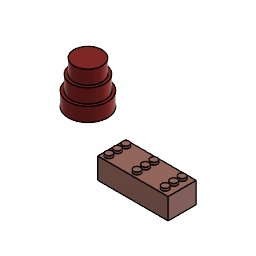
elipse (Autodesk Fusion 360 design; units mm, degrees)
part number: 2026-08-22-14-53-42-305
Autodesk Fusion 360 part; units mm, degrees
sketch "Sketch1" plane through (0, 0, 0) normal (0, 1, 0) x (1, 0, 0)
  ellipse E0 centre (13.4797, -9.3132) end of major axis (-45.8309, 16.9109) minor radius 24.1284
  line L0 (72.7902, -35.5373) -> (-45.8309, 16.9109) construction
  line L1 (23.2368, 12.7543) -> (3.7225, -31.3808) construction
  constraint coincident E0 L0.start
  constraint coincident E0 L0.end
  constraint coincident E0 L1.start
  constraint coincident E0 L1.end
sketch "Sketch2" plane through (0, 0, 0) normal (0, -1, 0) x (1, 0, 0)
  ellipse E0 centre (13.4797, 9.3132) end of major axis (-45.8309, -16.9109) minor radius 24.1284
  arc A0 (72.4234, 36.2739) -> (60.6973, -35.3427) centre (12.6561, 9.2916) ccw
  line L0 (-160.8173, -80.7542) -> (-249.1179, -79.1962) construction
  line L1 (-249.1179, -79.1962) -> (-248.7164, -56.4403) construction
  line L2 (-248.7164, -56.4403) -> (-160.4158, -57.9983) construction
  line L3 (-160.4158, -57.9983) -> (-160.8173, -80.7542) construction
  circle A1 centre (-98.7081, 34.943) radius 10
  circle A2 centre (-98.7081, 34.943) radius 12
  circle A3 centre (-98.7081, 34.943) radius 14
  dimension "d5" = 10
  dimension "d7" = 20
  dimension "d8" = 2
  dimension "d9" = 2
  constraint coincident E0 A0.start
  measures "d7" diameter of A1
sketch "Sketch3" plane through (0, 0, 0) normal (0, -1, 0) x (1, 0, 0)
extrude "Extrude6" add sketch "Sketch2" against normal blind 30 contours A1 makes body 1
extrude "Extrude7" add sketch "Sketch2" against normal blind 20 contours A2 bodies 1
extrude "Extrude8" add sketch "Sketch2" against normal blind 10 contours A3 bodies 1
sketch "Sketch4" plane through (0, 0, 0) normal (0, 1, 0) x (1, 0, 0)
sketch "Sketch5" plane through (0, 0, 0) normal (0, 1, 0) x (1, 0, 0)
sketch "restangulr" plane through (0, 0, 0) normal (0, 1, 0) x (1, 0, 0)
  line L0 (-49.8769, -76.8717) -> (0.1231, -76.8717)
  line L1 (0.1231, -76.8717) -> (0.1231, -56.8717)
  line L2 (0.1231, -56.8717) -> (-49.8769, -56.8717)
  line L3 (-49.8769, -56.8717) -> (-49.8769, -76.8717)
  dimension "d23" = 50
  dimension "d24" = 20
  dimension "d25" = 0.1231
  dimension "d26" = 56.8717
  constraint horizontal L0
  constraint vertical L1
  constraint horizontal L2
  constraint vertical L3
  measures "d23" distance of L1 L3
  measures "d24" distance of L0 L2
  measures "d25" distance of origin L1
  measures "d26" distance of origin L2
sketch "Sketch7" plane through (0, 0, 0) normal (0, 1, 0) x (1, 0, 0)
extrude "Extrude9" add sketch "restangulr" along normal blind 15 separate body makes body 2
sketch "Sketch8" plane through (0, 15, 0) normal (0, 1, 0) x (-1, 0, 0)
  line L0 (49.8769, 56.8717) -> (49.8769, 76.8717)
  line L1 (49.8769, 76.8717) -> (-0.1231, 76.8717)
  line L2 (-0.1231, 76.8717) -> (-0.1231, 56.8717)
  line L3 (-0.1231, 56.8717) -> (49.8769, 56.8717)
  circle A0 centre (45.9769, 60.7717) radius 2.5
  dimension "d29" = 5
  dimension "d30" = 3.9
  dimension "d31" = 3.9
  measures "d29" diameter of A0
  measures "d30" vertical distance of L0.start A0.centre
  measures "d31" horizontal distance of L0.start A0.centre
extrude "Extrude10" add sketch "Sketch8" along normal blind 1.7 contours A0 bodies 2
pattern_linear "R-Pattern1" count 3 spacing 20 along (1, 0, 0) count 3 spacing 6 along (0, 0, 1) of "Extrude10"
shell "Shell1" thickness 2 removed faces 1 at (-33.2102, 0, 63.5384) on bodies 2
equation "d6 = 'King Shohan'"
